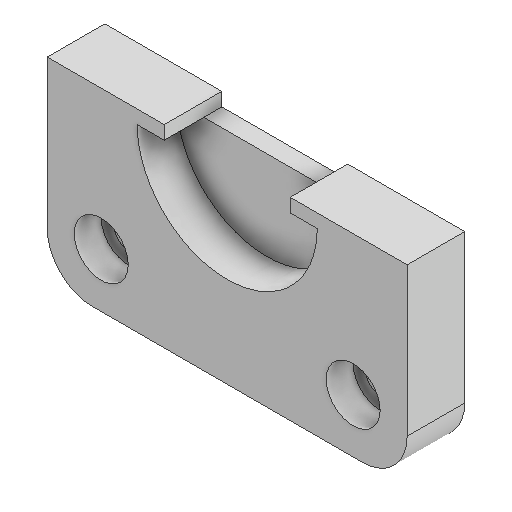
# Autodesk Inventor part: 零件8
Saved by Autodesk Inventor 2027 (Build 310192060, 192F)
## iProperties
Created: 2026-11-23
Part Number: 零件8
Material: 一般
Document SubType Name: Modeling
Designer: 王翊丞
Density: 1 g/cm^3
Appearance: 預設
Author: 王翊丞
Autodesk Inventor part; units mm, degrees
ref_plane "YZ Plane" through (0, 0, 0) normal (1, 0, 0) x (0, 1, 0)
ref_plane "工作平面1" through (11.1342, -2.9474, -11.5226) normal (0, 0, -1) x (-1, 0, 0)
sketch "草圖1" plane through (11.1342, -2.9474, -11.5226) normal (0, 0, -1) x (-1, 0, 0)
  spline S0 degree 3 poles (-10, 3.3359) (-10, 2.6974) (-9.9374, 2.059) (-9.5214, -0.0432) (-8.8844, -1.4489) (-7.1414, -3.7261) (-6.0868, -4.6346) (-3.9787, -5.8062) (-2.982, -6.1706) (-1.3104, -6.5002) (-0.6552, -6.5641) (0, -6.5641) (0.6552, -6.5641) (1.3104, -6.5002) (2.982, -6.1706) (3.9787, -5.8062) (6.0868, -4.6346) (7.1414, -3.7261) (8.8844, -1.4489) (9.5214, -0.0432) (9.9374, 2.059) (10, 2.6974) (10, 3.3359) knots -3.061517 -3.061517 -3.061517 -3.061517 -2.875848 -2.875848 -2.438352 -2.438352 -2.041645 -2.041645 -1.736485 -1.736485 -1.545761 -1.545761 -1.545761 -1.355036 -1.355036 -1.049877 -1.049877 -0.653169 -0.653169 -0.215674 -0.215674 -0.030005 -0.030005 -0.030005 -0.030005 projected
  line L0 (10, 3.3359) -> (-10, 3.3359) projected
  line L1 (-20, 3.3359) -> (20, 3.3359)
  line L2 (-20, 3.3359) -> (20, 3.3359)
  line L3 (20, 3.3359) -> (20, -16.6641)
  line L4 (20, -16.6641) -> (-20, -16.6641)
  line L5 (-20, -16.6641) -> (-20, 3.3359)
  point P0 (11.1342, 2.9474)
  point P1 (0, 3.3359)
  point P2 (10, 3.3359)
  dimension "d0" = 40
  dimension "d1" = 20
  constraints: 10 end point, 2 horizontal, 2 midpoint, 2 parallel, 1 perpendicular, 1 point on line
  measures "d0" distance of L1.start L1.end
  measures "d1" distance of L2.end L3.end
ref_plane "工作平面2" through (1.43, -9.2205, -4.1226) normal (0, 0, 1) x (1, 0, 0)
extrude "擠出1" add sketch "草圖1" against normal up to surface (7.4 mm away) contours S0 L1 L3 L4 L5
sketch "草圖2" plane through (11.1342, -2.9474, -11.5226) normal (0, 0, -1) x (-1, 0, 0)
  point P0 (11.1342, 2.9474)
sketch "草圖3" plane through (11.1342, -2.9474, -11.5226) normal (0, 0, -1) x (-1, 0, 0)
  line L0 (-20, -16.6641) -> (20, -16.6641) projected
  line L1 (20, -16.6641) -> (20, 3.3359) projected
  line L2 (20, 3.3359) -> (10, 3.3359) projected
  line L3 (-10, 3.3359) -> (-20, 3.3359) projected
  line L4 (-20, 3.3359) -> (-20, -16.6641) projected
  line L5 (-10, 3.3359) -> (10, 3.3359)
  point P0 (11.1342, 2.9474)
  constraints: 2 end point, 1 horizontal, 1 horizontal alignment
extrude "擠出2" add sketch "草圖3" along normal blind 2
sketch "草圖4" plane through (11.1342, -2.9474, -13.5226) normal (0, 0, -1) x (-1, 0, 0)
  line L0 (-20, 3.3359) -> (-20, -16.6641) projected
  line L1 (-20, -16.6641) -> (20, -16.6641) projected
  line L2 (20, -16.6641) -> (20, 3.3359) projected
  line L3 (20, 3.3359) -> (-20, 3.3359) projected
  circle A0 centre (-14, -10.6641) radius 2.6
  circle A1 centre (14, -10.6641) radius 2.6
  point P0 (11.1342, 2.9474)
  dimension "d6" = 5.2
  dimension "d7" = 6
  dimension "d8" = 6
  dimension "d9" = 6
  dimension "d10" = 6
  constraints: 2 centre point, 1 equal radius
  measures "d6" diameter of A0
  measures "d7" distance from line of L0 A0.centre
  measures "d8" distance from line of L1 A0.centre
  measures "d9" distance from line of L2 A1.centre
  measures "d10" distance from line of L1 A1.centre
extrude "擠出3" cut sketch "草圖4" against normal blind 5 contours A0 | A1
sketch "草圖5" plane through (11.1342, -2.9474, -13.5226) normal (0, 0, -1) x (-1, 0, 0)
  line L0 (-6, 3.3359) -> (-6, 16.0359) projected
  line L1 (6, 16.0359) -> (6, 3.3359) projected
  line L2 (20, 3.3359) -> (-20, 3.3359) projected
  line L3 (-20, 3.3359) -> (-7, 3.3359)
  line L4 (-7, 3.3359) -> (-7, 4.8359)
  line L5 (-7, 4.8359) -> (-20, 4.8359)
  line L6 (-20, 4.8359) -> (-20, 3.3359)
  line L7 (20, 3.3359) -> (7, 3.3359)
  line L8 (7, 3.3359) -> (7, 4.8359)
  line L9 (7, 4.8359) -> (20, 4.8359)
  line L10 (20, 4.8359) -> (20, 3.3359)
  point P0 (11.1342, 2.9474)
  point P1 (-7, 3.3359)
  dimension "d13" = 1.5
  dimension "d14" = 1
  constraints: 16 end point, 4 parallel, 2 horizontal, 2 perpendicular, 1 collinear, 1 point on line
  measures "d13" distance between parallel lines of L2 L5
  measures "d14" distance between parallel lines of L0 L4
extrude "擠出4" add sketch "草圖5" against normal up to surface (9.4 mm away)
fillet "圓角1" radius 5 2 edges at (31.1342, -19.6116, -8.8226) (-8.8658, -19.6116, -8.8226)
sketch "草圖6" plane through (18.1342, 1.8884, -4.1226) normal (0, 0, 1) x (1, 0, 0)
  arc A0 (-27, -16.5) -> (-22, -21.5) centre (-22, -16.5) ccw projected
  line L0 (8, -21.5) -> (-22, -21.5) projected
  arc A1 (8, -21.5) -> (13, -16.5) centre (8, -16.5) ccw projected
  line L1 (13, 0) -> (13, -16.5) projected
  line L2 (0, 0) -> (13, 0) projected
  line L3 (0, -1.5) -> (0, 0) projected
  line L4 (3, -1.5) -> (0, -1.5) projected
  spline S0 degree 3 poles (-17, -1.5) (-17, -2.1384) (-16.9374, -2.7769) (-16.5214, -4.8791) (-15.8844, -6.2848) (-14.1414, -8.562) (-13.0868, -9.4705) (-10.9787, -10.6421) (-9.982, -11.0065) (-8.3104, -11.3361) (-7.6552, -11.4) (-7, -11.4) (-6.3448, -11.4) (-5.6896, -11.3361) (-4.018, -11.0065) (-3.0213, -10.6421) (-0.9132, -9.4705) (0.1414, -8.562) (1.8844, -6.2848) (2.5214, -4.8791) (2.9374, -2.7769) (3, -2.1384) (3, -1.5) knots 0 0 0 0 0.061246 0.061246 0.205562 0.205562 0.336423 0.336423 0.437086 0.437086 0.5 0.5 0.5 0.562914 0.562914 0.663577 0.663577 0.794438 0.794438 0.938754 0.938754 1 1 1 1 projected
  line L5 (-14, -1.5) -> (-17, -1.5) projected
  line L6 (-14, 0) -> (-14, -1.5) projected
  line L7 (-27, 0) -> (-14, 0) projected
  line L8 (-27, -16.5) -> (-27, 0) projected
  point P0 (-18.1342, -1.8884)
  constraints: 1 horizontal alignment
extrude "擠出5" cut sketch "草圖6" against normal blind 3
sketch "草圖7" plane through (11.1342, -2.9474, -13.5226) normal (0, 0, -1) x (-1, 0, 0)
  circle A0 centre (14, -10.6641) radius 2.6 projected
  circle A1 centre (-14, -10.6641) radius 2.6 projected
  arc A2 (15, -16.6641) -> (20, -11.6641) centre (15, -11.6641) ccw projected
  line L0 (20, -11.6641) -> (20, 4.8359) projected
  line L1 (20, 4.8359) -> (7, 4.8359) projected
  line L2 (7, 4.8359) -> (7, 3.3359) projected
  line L3 (7, 3.3359) -> (-7, 3.3359) projected
  line L4 (-7, 3.3359) -> (-7, 4.8359) projected
  line L5 (-7, 4.8359) -> (-20, 4.8359) projected
  line L6 (-20, 4.8359) -> (-20, -11.6641) projected
  arc A3 (-20, -11.6641) -> (-15, -16.6641) centre (-15, -11.6641) ccw projected
  line L7 (-15, -16.6641) -> (15, -16.6641) projected
  circle A4 centre (-14, -10.6641) radius 1.6
  circle A5 centre (14, -10.6641) radius 1.6
  point P0 (11.1342, 2.9474)
  dimension "d20" = 3.2
  dimension "d21" = 3.2
  constraints: 2 centre point, 2 coincident
  measures "d20" diameter of A4
  measures "d21" diameter of A5
extrude "擠出6" add sketch "草圖7" against normal up to surface (5 mm away) contours A0 | A1
extrude "擠出7" cut sketch "草圖7" against normal through all contours A4 | A5
sketch "草圖8" plane through (18.1342, 1.8884, -7.1226) normal (0, 0, 1) x (1, 0, 0)
  circle A0 centre (7, -15.5) radius 1.6 projected
  circle A1 centre (-21, -15.5) radius 1.6 projected
  arc A2 (-27, -16.5) -> (-22, -21.5) centre (-22, -16.5) ccw projected
  line L0 (8, -21.5) -> (-22, -21.5) projected
  arc A3 (8, -21.5) -> (13, -16.5) centre (8, -16.5) ccw projected
  line L1 (13, 0) -> (13, -16.5) projected
  line L2 (0, 0) -> (13, 0) projected
  line L3 (0, -1.5) -> (0, 0) projected
  line L4 (3, -1.5) -> (0, -1.5) projected
  line L5 (-14, -1.5) -> (-17, -1.5) projected
  line L6 (-14, 0) -> (-14, -1.5) projected
  line L7 (-27, 0) -> (-14, 0) projected
  line L8 (-27, -16.5) -> (-27, 0) projected
  point P0 (-18.1342, -1.8884)
  constraints: 1 horizontal alignment
hole "孔1" at (-2.8658, -13.6116, -7.1226) at (25.1342, -13.6116, -7.1226) direction (0, 0, -1) diameter 6 depth 3
